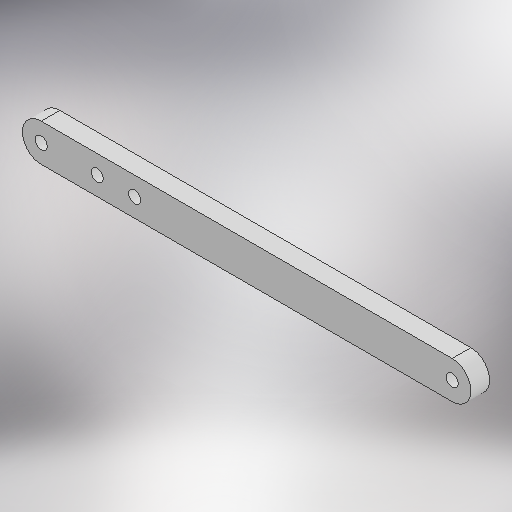
# Autodesk Inventor part: 3D_link1
Saved by Autodesk Inventor 2025.3 (Build 293356030, 356C)
## iProperties
Created: 2026-05-21
Part Number: 3D_link1
Material: 一般
Document SubType Name: Modeling
Designer: ibuki_ono
Density: 1 g/cm^3
Appearance: 既定
Author: ibuki_ono
Autodesk Inventor part; units mm, degrees
ref_plane "YZ Plane" through (0, 0, 0) normal (1, 0, 0) x (0, 1, 0)
ref_plane "XZ Plane" through (0, 0, 0) normal (0, 1, 0) x (-1, 0, 0)
ref_plane "XY Plane" through (0, 0, 0) normal (0, 0, 1) x (1, 0, 0)
sketch "スケッチ1" plane through (0, 0, 0) normal (0, 0, 1) x (1, 0, 0)
  line L0 (-55, 0) -> (55, 0) construction
  line L1 (-55, -5) -> (55, -5)
  line L2 (55, 5) -> (-55, 5)
  arc A0 (-55, 5) -> (-55, -5) centre (-55, 0) ccw
  arc A1 (55, -5) -> (55, 5) centre (55, 0) ccw
  line L3 (0, 0) -> (110, 0) construction
  dimension "d0" = 55
  dimension "d1" = 0
  dimension "d2" = 10
  constraints: 10 end point, 4 point on circle, 4 tangent, 2 centre point, 2 horizontal, 1 collinear, 1 midpoint, 1 parallel
  measures "d0" distance of L3.start L0.end
  measures "d1" distance between parallel lines of L0 L3
  measures "d2" diameter of A1
extrude "押し出し1" add sketch "スケッチ1" along normal mid plane 5
sketch "スケッチ2" plane through (0, 0, 2.5) normal (0, 0, 1) x (1, 0, 0)
  arc A0 (-55, 5) -> (-55, -5) centre (-55, 0) ccw projected
  arc A1 (55, -5) -> (55, 5) centre (55, 0) ccw projected
  line L0 (-55, 0) -> (-40, 0) construction
  line L1 (-55, 0) -> (-40, 0) construction
  line L2 (-40, 0) -> (-30, 0) construction
  line L3 (-40, 0) -> (-30, 0) construction
  point P0 (0, 0)
  dimension "d26" = 15
  dimension "d27" = 0
  dimension "d28" = 10
  dimension "d29" = 0
  constraints: 8 end point, 4 horizontal, 2 coincident, 2 collinear
  measures "d26" distance of L0.start L0.end
  measures "d27" distance between parallel lines of L0 L1
  measures "d28" distance of L2.start L2.end
  measures "d29" distance between parallel lines of L2 L3
hole "穴1" at (-55, 0, 2.5) at (55, 0, 2.5) at (-40, 0, 2.5) at (-30, 0, 2.5) direction (0, 0, -1) diameter 3.2 end through all
